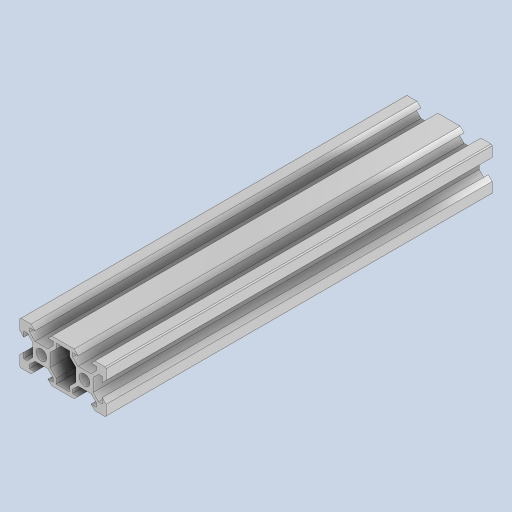
# Autodesk Inventor part: Perfil de alumínio perpendicular
Saved by Autodesk Inventor 2024.3 (Build 283343000, 343)
## iProperties
Created: 2023-03-24
Part Number: Perfil de alumínio perpendicular
Material: Alumínio 6061
Document SubType Name: Modeling
Designer: robof
Density: 2.86009 g/cm^3
Appearance: Alumínio - Escuro
Mass: 647.2 g
Surface Area: 2424.91 cm^2
Volume: 226.286 cm^3
Author: robof
Autodesk Inventor part; units mm, degrees
ref_plane "YZ Plane" through (0, 0, 0) normal (1, 0, 0) x (0, 1, 0)
ref_plane "XZ Plane" through (0, 0, 0) normal (0, 1, 0) x (-1, 0, 0)
ref_plane "XY Plane" through (0, 0, 0) normal (0, 0, 1) x (1, 0, 0)
sketch "Sketch1" plane through (0, 0, 0) normal (0, 0, 1) x (1, 0, 0)
  line L0 (-9.5, 10) -> (-4.8, 10)
  line L1 (4.8, 10) -> (9.5, 10)
  line L2 (-3.0101, 4) -> (3.0101, 4)
  line L3 (4, 3.0101) -> (4, -4)
  line L4 (3.0101, -4) -> (-3.0101, -4)
  line L5 (-4, -3.0101) -> (-4, 4)
  line L6 (-4.8, 10) -> (-3, 8.2)
  line L7 (4.8, 10) -> (3, 8.2)
  line L8 (3, 8.2) -> (-3, 8.2)
  circle A0 centre (0, 0) radius 2.5
  line L9 (-10, -4.8) -> (-8.2, -3)
  line L10 (-8.2, 3) -> (-8.2, -3)
  line L11 (-10, 4.8) -> (-8.2, 3)
  line L12 (4.8, -10) -> (3, -8.2)
  line L13 (-3, -8.2) -> (3, -8.2)
  line L14 (-4.8, -10) -> (-3, -8.2)
  line L15 (10, 4.8) -> (8.2, 3)
  line L16 (8.2, -3) -> (8.2, 3)
  line L17 (10, -4.8) -> (8.2, -3)
  line L18 (-4.8, -10) -> (-9.5, -10)
  line L19 (10, 9.5) -> (10, 4.8)
  line L20 (10, -4.8) -> (10, -9.5)
  line L21 (9.5, -10) -> (4.8, -10)
  line L22 (-4, 3.0101) -> (-6.9, 5.9101)
  line L23 (-3.0101, 4) -> (-5.5, 6.4899)
  line L24 (3.0101, 4) -> (5.5, 6.4899)
  line L25 (4.9899, 4) -> (6.4899, 5.5)
  line L26 (-3.0101, -4) -> (-5.5, -6.4899)
  line L27 (-4, -3.0101) -> (-6.9, -5.9101)
  line L28 (3.0101, -4) -> (5.5, -6.4899)
  line L29 (4, -3.0101) -> (6.4899, -5.5)
  line L30 (-8.2, 3) -> (-8.2, 5.5)
  line L31 (-8.2, -3) -> (-8.2, -5.5)
  line L32 (-3, -8.2) -> (-5.5, -8.2)
  line L33 (-5.5, -8.2) -> (3, -8.2)
  line L34 (5.5, -8.2) -> (3, -8.2)
  line L35 (8.2, 3) -> (8.2, 5.5)
  line L36 (8.2, -3) -> (8.2, -5.5)
  line L37 (3, 8.2) -> (5.5, 8.2)
  line L38 (-3, 8.2) -> (-5.5, 8.2)
  arc A1 (10, 9.5) -> (9.5, 10) centre (9.5, 9.5) ccw
  arc A2 (9.5, -10) -> (10, -9.5) centre (9.5, -9.5) ccw
  line L39 (-5.5, 8.2) -> (-5.5, 6.4899)
  line L40 (5.5, 6.4899) -> (5.5, 8.2)
  line L41 (-8.2, -3) -> (-8.2, -5.5)
  line L42 (-8.2, -5.5) -> (-6.4899, -5.5)
  line L43 (-4, -3.0101) -> (-6.4899, -5.5)
  line L44 (-4, 3.0101) -> (-6.4899, 5.5)
  line L45 (-6.4899, 5.5) -> (-8.2, 5.5)
  line L46 (-8.2, 3) -> (-8.2, 5.5)
  line L47 (3, -8.2) -> (5.5, -8.2)
  line L48 (5.5, -8.2) -> (5.5, -6.4899)
  line L49 (3.0101, -4) -> (5.5, -6.4899)
  line L50 (-3.0101, -4) -> (-5.5, -6.4899)
  line L51 (-5.5, -6.4899) -> (-5.5, -8.2)
  line L52 (-3, -8.2) -> (-5.5, -8.2)
  line L53 (8.2, 3) -> (8.2, 5.5)
  line L54 (8.2, 5.5) -> (6.4899, 5.5)
  line L55 (4, 3.0101) -> (6.4899, 5.5)
  line L56 (4, -3.0101) -> (6.4899, -5.5)
  line L57 (6.4899, -5.5) -> (8.2, -5.5)
  line L58 (8.2, -3) -> (8.2, -5.5)
  line L59 (-4.8, 10) -> (-15.2, 10)
  line L60 (-24.8, 10) -> (-29.5, 10)
  line L61 (-16.9899, 4) -> (-23.0101, 4)
  line L62 (-24, 3.0101) -> (-24, -4)
  line L63 (-23.0101, -4) -> (-16.9899, -4)
  line L64 (-16, -3.0101) -> (-16, 4)
  line L65 (-15.2, 10) -> (-17, 8.2)
  line L66 (-24.8, 10) -> (-23, 8.2)
  line L67 (-23, 8.2) -> (-17, 8.2)
  circle A3 centre (-20, 0) radius 2.5
  line L68 (-24.8, -10) -> (-23, -8.2)
  line L69 (-17, -8.2) -> (-23, -8.2)
  line L70 (-15.2, -10) -> (-17, -8.2)
  line L71 (-30, 4.8) -> (-28.2, 3)
  line L72 (-28.2, -3) -> (-28.2, 3)
  line L73 (-30, -4.8) -> (-28.2, -3)
  line L74 (-15.2, -10) -> (-4.8, -10)
  line L75 (-30, 9.5) -> (-30, 4.8)
  line L76 (-30, -4.8) -> (-30, -9.5)
  line L77 (-29.5, -10) -> (-24.8, -10)
  line L78 (-16, 3.0101) -> (-13.1, 5.9101)
  line L79 (-16.9899, 4) -> (-14.5, 6.4899)
  line L80 (-23.0101, 4) -> (-25.5, 6.4899)
  line L81 (-24.9899, 4) -> (-26.4899, 5.5)
  line L82 (-16.9899, -4) -> (-14.5, -6.4899)
  line L83 (-16, -3.0101) -> (-13.1, -5.9101)
  line L84 (-23.0101, -4) -> (-25.5, -6.4899)
  line L85 (-24, -3.0101) -> (-26.4899, -5.5)
  line L86 (-17, -8.2) -> (-14.5, -8.2)
  line L87 (-25.5, -8.2) -> (-23, -8.2)
  line L88 (-28.2, 3) -> (-28.2, 5.5)
  line L89 (-28.2, -3) -> (-28.2, -5.5)
  line L90 (-23, 8.2) -> (-25.5, 8.2)
  arc A4 (-29.5, 10) -> (-30, 9.5) centre (-29.5, 9.5) ccw
  arc A5 (-30, -9.5) -> (-29.5, -10) centre (-29.5, -9.5) ccw
  line L91 (-14.5, 8.2) -> (-14.5, 6.4899)
  line L92 (-25.5, 6.4899) -> (-25.5, 8.2)
  line L93 (-16, -3.0101) -> (-13.5101, -5.5)
  line L94 (-16, 3.0101) -> (-13.5101, 5.5)
  line L95 (-23, -8.2) -> (-25.5, -8.2)
  line L96 (-25.5, -8.2) -> (-25.5, -6.4899)
  line L97 (-23.0101, -4) -> (-25.5, -6.4899)
  line L98 (-16.9899, -4) -> (-14.5, -6.4899)
  line L99 (-14.5, -6.4899) -> (-14.5, -8.2)
  line L100 (-17, -8.2) -> (-14.5, -8.2)
  line L101 (-28.2, 3) -> (-28.2, 5.5)
  line L102 (-28.2, 5.5) -> (-26.4899, 5.5)
  line L103 (-24, 3.0101) -> (-26.4899, 5.5)
  line L104 (-24, -3.0101) -> (-26.4899, -5.5)
  line L105 (-26.4899, -5.5) -> (-28.2, -5.5)
  line L106 (-28.2, -3) -> (-28.2, -5.5)
  line L107 (-13.4, 8.2) -> (-13.1, 8.2)
  line L108 (-13.1, 8.2) -> (-13.1, 5.9101)
  line L109 (-13.1, -5.9101) -> (-13.1, -8.2)
  line L110 (-6.6, -8.2) -> (-6.9, -8.2)
  line L111 (-6.9, -8.2) -> (-6.9, 8.2)
  line L112 (-17, 8.2) -> (-14.5, 8.2)
  line L113 (-13.1, 8.2) -> (-6.9, 8.2)
  line L114 (-6.9, -8.2) -> (-13.1, -8.2)
  line L115 (-14.5, -8.2) -> (-23, -8.2)
  point P0 (0, 10)
  point P1 (10, -10)
  point P2 (-8.2, 7.2101)
  point P3 (7.2101, -8.2)
  point P4 (8.2, -7.2101)
  point P5 (-6.3225, 5.3325)
  point P6 (-5.1101, 6.1)
  point P7 (6.57, -5.58)
  point P8 (6.195, 5.205)
  point P9 (5.1101, 6.1)
  point P10 (0, 7.2057)
  point P11 (0, 8.2)
  point P12 (-6.1, -5.1101)
  point P13 (-6.1, 5.1101)
  point P14 (5.1101, -6.1)
  point P15 (-5.1101, -6.1)
  point P16 (6.1, 5.1101)
  point P17 (6.1, -5.1101)
  point P18 (-20, 10)
  point P19 (-30, -10)
  point P20 (-27.2101, -8.2)
  point P21 (-28.2, -7.2101)
  point P22 (-20, 7.2057)
  point P23 (-20, 8.2)
  point P24 (-6.9, 5.5)
  point P25 (-6.9, -5.5)
  dimension "d2" = 9.6
  dimension "d6" = 6
  dimension "d9" = 5
  dimension "d10" = 1.8
  dimension "d13" = 360
  dimension "d37" = 360
  dimension "d39" = 1.4
  dimension "d40" = 1.4
  constraints: 232 end point, 37 point on line, 10 perpendicular, 8 point on circle, 6 centre point, 5 horizontal, 4 tangent, 2 coincident, 2 collinear, 2 parallel, 2 vertical alignment, 1 midpoint, 1 vertical, 94 other
  measures "d2" distance of L0.end L1.start
  measures "d6" distance of L7.end L6.end
  measures "d9" diameter of A0
  measures "d10" distance between parallel lines of L8 L1
  measures "d39" distance of L91.start L107.end
  measures "d40" distance of L110.end L32.end
extrude "Extrusion1" add sketch "Sketch1" against normal blind 179 contours L0 L6 L38 L39 L23 L2 L24 L40 L37 L7 L1 A1 L19 L15 L35 L54 L25 L55 L3 L29 L57 L36 L17 L20 A2 L21 L12 L34 L48 L28 L4 L26 L51 L32 L14 L18 L74 L70 L86 L99 L82 L63 L84 L96 L87 L68 L77 A5 L76 L73 L89 L105 L85 L62 L103 L81 L102 L88 L71 L75 A4 L60 L66 L90 L92 L80 L61 L79 L91 L112 L65 L59
